Autodesk Inventor part; units mm, degrees
(part 2 of 2)
sketch "Boceto2" plane through (0, 0, 0) normal (0, 0, 1) x (1, 0, 0)
  spline S0 degree 3 poles (7.9309, 35.7631) (6.9516, 35.763) (3.1923, 28.7681) (4.1998, 28.3225) (4.6339, 28.1306) (10.2939, 27.728) (11.664, 28.3225) (12.6319, 28.7425) (8.957, 35.7632) (7.9309, 35.7631) knots 0 0 0 0 1 1 1 2 2 2 3 3 3 3 projected
  line L0 (7.3637, 34.0871) -> (8.4981, 34.0871) projected
  line L1 (7.4884, 30.4763) -> (7.3637, 34.0871) projected
  line L2 (8.4981, 34.0871) -> (8.3734, 30.4763) projected
  line L3 (8.3734, 30.4763) -> (7.4884, 30.4763) projected
  circle A0 centre (7.9309, 29.3763) radius 0.65 projected
  line L4 (32.3701, 25.3428) -> (32.3701, 0.7726)
  line L5 (32.3701, 7.2118) -> (27.7914, 7.2118)
  line L6 (27.7914, 7.2118) -> (27.7914, 6.0248)
  line L7 (26.7914, 5.0248) -> (26.4708, 5.0248)
  line L8 (25.4708, 6.0248) -> (25.4708, 7.2118)
  line L9 (25.4708, 7.2118) -> (24.0793, 7.2118)
  line L10 (24.0793, 7.2118) -> (24.0793, 14.3592)
  line L11 (24.0793, 14.3592) -> (24.8752, 19.7039)
  line L12 (26.1237, 21.2714) -> (26.3897, 21.3756)
  line L13 (31.8621, 22.4095) -> (32.3701, 22.4095)
  arc A1 (31.8621, 22.4095) -> (26.3897, 21.3756) centre (31.8621, 7.4095) ccw
  arc A2 (26.1237, 21.2714) -> (24.8752, 19.7039) centre (26.8534, 19.4093) ccw
  arc A3 (25.4708, 6.0248) -> (26.4708, 5.0248) centre (26.4708, 6.0248) ccw
  arc A4 (26.7914, 5.0248) -> (27.7914, 6.0248) centre (26.7914, 6.0248) ccw
  line L14 (32.3701, 21.0432) -> (28.8161, 21.0432)
  line L15 (28.4161, 20.6432) -> (28.4161, 20.6432)
  line L16 (28.8161, 20.2432) -> (32.3701, 20.2432)
  arc A5 (28.8161, 21.0432) -> (28.4161, 20.6432) centre (28.8161, 20.6432) ccw
  arc A6 (28.4161, 20.6432) -> (28.8161, 20.2432) centre (28.8161, 20.6432) ccw
  line L17 (32.3701, 19.3042) -> (26.6019, 19.3042)
  line L18 (26.2062, 18.9626) -> (25.5385, 14.4443)
  line L19 (25.9342, 13.9858) -> (32.3701, 13.9858)
  arc A7 (25.5385, 14.4443) -> (25.9342, 13.9858) centre (25.9342, 14.3858) ccw
  arc A8 (26.6019, 19.3042) -> (26.2062, 18.9626) centre (26.6019, 18.9042) ccw
  ellipse E0 centre (26.6311, 10.5064) end of major axis (25.5385, 10.5064) minor radius 0.9943
  line L20 (32.3701, 7.2118) -> (36.9488, 7.2118)
  line L21 (36.9488, 7.2118) -> (36.9488, 6.0248)
  line L22 (37.9488, 5.0248) -> (38.2694, 5.0248)
  line L23 (39.2694, 6.0248) -> (39.2694, 7.2118)
  line L24 (39.2694, 7.2118) -> (40.6609, 7.2118)
  line L25 (40.6609, 7.2118) -> (40.6609, 14.3592)
  line L26 (40.6609, 14.3592) -> (39.8649, 19.7039)
  line L27 (38.6164, 21.2714) -> (38.3505, 21.3756)
  line L28 (32.878, 22.4095) -> (32.3701, 22.4095)
  arc A9 (38.3505, 21.3756) -> (32.878, 22.4095) centre (32.878, 7.4095) ccw
  arc A10 (39.8649, 19.7039) -> (38.6164, 21.2714) centre (37.8867, 19.4093) ccw
  arc A11 (38.2694, 5.0248) -> (39.2694, 6.0248) centre (38.2694, 6.0248) ccw
  arc A12 (36.9488, 6.0248) -> (37.9488, 5.0248) centre (37.9488, 6.0248) ccw
  line L29 (32.3701, 21.0432) -> (35.9241, 21.0432)
  line L30 (36.3241, 20.6432) -> (36.3241, 20.6432)
  line L31 (35.9241, 20.2432) -> (32.3701, 20.2432)
  arc A13 (36.3241, 20.6432) -> (35.9241, 21.0432) centre (35.9241, 20.6432) ccw
  arc A14 (35.9241, 20.2432) -> (36.3241, 20.6432) centre (35.9241, 20.6432) ccw
  line L32 (32.3701, 19.3042) -> (38.1382, 19.3042)
  line L33 (38.5339, 18.9626) -> (39.2016, 14.4443)
  line L34 (38.8059, 13.9858) -> (32.3701, 13.9858)
  arc A15 (38.8059, 13.9858) -> (39.2016, 14.4443) centre (38.8059, 14.3858) ccw
  arc A16 (38.5339, 18.9626) -> (38.1382, 19.3042) centre (38.1382, 18.9042) ccw
  ellipse E1 centre (38.1091, 10.5064) end of major axis (39.2016, 10.5064) minor radius 0.9943
  line L35 (7.9309, 33.6763) -> (7.9309, 9.1164)
  line L36 (7.9309, 29.1763) -> (4.7309, 29.1763)
  line L37 (4.7309, 28.5763) -> (7.9309, 28.5763)
  arc A17 (4.7309, 29.1763) -> (4.4309, 28.8763) centre (4.7309, 28.8763) ccw
  arc A18 (4.4309, 28.8763) -> (4.7309, 28.5763) centre (4.7309, 28.8763) ccw
  arc A19 (11.1309, 28.5763) -> (11.4309, 28.8763) centre (11.1309, 28.8763) ccw
  arc A20 (11.4309, 28.8763) -> (11.1309, 29.1763) centre (11.1309, 28.8763) ccw
  line L38 (11.1309, 28.5763) -> (7.9309, 28.5763)
  line L39 (7.9309, 29.1763) -> (11.1309, 29.1763)
  line L40 (24.7872, 19.1125) -> (25.3084, 22.6124)
  line L41 (32.3947, 25.3417) -> (32.3701, 25.3428)
  arc A21 (32.3947, 25.3417) -> (26.8076, 24.5197) centre (31.7456, 10.3558) ccw
  line L42 (25.7305, 23.6251) -> (25.551, 23.3118)
  arc A22 (26.8076, 24.5197) -> (25.7305, 23.6251) centre (27.466, 22.6312) ccw
  arc A23 (25.551, 23.3118) -> (25.3084, 22.6124) centre (27.2865, 22.3178) ccw
  line L43 (39.953, 19.1125) -> (39.4318, 22.6124)
  arc A24 (37.9325, 24.5197) -> (32.3454, 25.3417) centre (32.9946, 10.3558) ccw
  line L44 (39.0097, 23.6251) -> (39.1891, 23.3118)
  arc A25 (39.0097, 23.6251) -> (37.9325, 24.5197) centre (37.2741, 22.6312) ccw
  arc A26 (39.4318, 22.6124) -> (39.1891, 23.3118) centre (37.4536, 22.3178) ccw
  line L45 (24.0793, 8.0227) -> (-63.9207, 8.0227)
  line L46 (24.0793, 11.5227) -> (-63.9207, 11.5227)
  line L47 (-65.9207, 13.5227) -> (-65.9207, 21.5227)
  line L48 (-65.9207, 6.0227) -> (-65.9207, -1.9773)
  line L49 (-69.9207, -1.9773) -> (-69.9207, 21.5227)
  arc A27 (-67.9207, 23.5227) -> (-69.9207, 21.5227) centre (-67.9207, 21.5227) ccw
  arc A28 (-65.9207, 21.5227) -> (-67.9207, 23.5227) centre (-67.9207, 21.5227) ccw
  arc A29 (-67.9207, -3.9773) -> (-65.9207, -1.9773) centre (-67.9207, -1.9773) ccw
  arc A30 (-69.9207, -1.9773) -> (-67.9207, -3.9773) centre (-67.9207, -1.9773) ccw
  arc A31 (-63.9207, 8.0227) -> (-65.9207, 6.0227) centre (-63.9207, 6.0227) ccw
  arc A32 (-65.9207, 13.5227) -> (-63.9207, 11.5227) centre (-63.9207, 13.5227) ccw
  line L50 (40.6609, 8.0227) -> (74.1609, 8.0227)
  line L51 (75.6609, 9.5227) -> (75.6609, 10.0227)
  line L52 (74.1609, 11.5227) -> (40.6609, 11.5227)
  line L53 (-16.0296, 22.7659) -> (-11.0296, 22.7659)
  line L54 (-11.0296, 22.7659) -> (-11.0296, 16.7659)
  line L55 (-11.0296, 16.7659) -> (-16.0296, 16.7659)
  line L56 (-11.0296, 19.7659) -> (-19.4903, 19.7659)
  line L57 (-16.0296, 22.7659) -> (-16.0296, 21.6659)
  line L58 (-16.0296, 21.6659) -> (-14.4296, 21.6659)
  line L59 (-14.4296, 21.6659) -> (-14.4296, 17.8659)
  line L60 (-14.4296, 17.8659) -> (-16.0296, 17.8659)
  line L61 (-16.0296, 17.8659) -> (-16.0296, 16.7659)
  arc A33 (75.6609, 10.0227) -> (74.1609, 11.5227) centre (74.1609, 10.0227) ccw
  arc A34 (74.1609, 8.0227) -> (75.6609, 9.5227) centre (74.1609, 9.5227) ccw
  point P0 (0, 0)
  point P1 (7.9309, 35.7631)
  point P2 (28.4161, 21.0432)
  point P3 (28.4161, 20.2432)
  point P4 (36.3241, 21.0432)
  point P5 (36.3241, 20.2432)
  point P6 (25.5317, 24.1125)
  point P7 (26.0869, 24.2475)
  point P8 (26.0869, 24.2475)
  point P9 (-65.9207, 8.0227)
  point P10 (-65.9207, 11.5227)
  point P11 (-65.9207, 23.5227)
  point P12 (-69.9207, 23.5227)
  point P13 (-65.9207, -3.9773)
  point P14 (-69.9207, -3.9773)
  point P15 (-67.9207, 23.5227)
  point P16 (-67.9207, -3.9773)
  point P17 (32.3703, 25.3428)
  point P18 (75.6609, 8.0227)
  point P19 (75.6609, 11.5227)
  point P20 (7.3124, 29.1763)
  point P21 (8.5494, 29.1763)
  dimension "d5" = 15
  dimension "d6" = 2
  dimension "d7" = 1
  dimension "d8" = 0.8
  dimension "d9" = 0.4
  dimension "d10" = 0.4
  dimension "d11" = 0.3
  dimension "d12" = 0.6
  dimension "d13" = 7
  dimension "d14" = 81.53
  dimension "d15" = 16.5816
  dimension "d16" = 14.9897
  dimension "d17" = 5
  dimension "d18" = 15
  dimension "d20" = 2
  dimension "d21" = 90
  dimension "d22" = 90
  dimension "d23" = 3.5
  dimension "d24" = 12
  dimension "d25" = 4
  dimension "d26" = 12
  dimension "d27" = 4
  dimension "d28" = 2
  dimension "d41" = 35
  dimension "d42" = 5
  dimension "d43" = 6
  dimension "d44" = 3.8
  dimension "d47" = 1.5
  dimension "d48" = 1.6
  constraints: 116 end point, 67 point on circle, 46 symmetric about line, 40 point on line, 35 centre point, 35 tangent, 18 horizontal, 13 vertical, 11 equal radius, 3 collinear, 1 midpoint, 33 other
  measures "d5" radius of A1
  measures "d6" radius of A2
  measures "d7" radius of A3
  measures "d8" distance of point (28.416, 21.043) point (28.416, 20.243)
  measures "d9" radius of A5
  measures "d10" radius of A7
  measures "d11" radius of A17
  measures "d12" distance between parallel lines of L37 L36
  measures "d13" distance of A17.end A20.start
  measures "d14" angle of L19 L11
  measures "d15" distance of L26.start L10.end
  measures "d16" distance of L26.end L11.end
  measures "d17" vertical distance of L40.start point (25.532, 24.113)
  measures "d18" radius of A21
  measures "d20" radius of A22
  measures "d21" distance of L45.start point (-65.921, 8.023)
  measures "d22" distance of L46.start point (-65.921, 11.523)
  measures "d23" distance between parallel lines of L45 L46
  measures "d24" distance of point (-65.921, 11.523) point (-65.921, 23.523)
  measures "d25" distance of point (-65.921, 23.523) point (-69.921, 23.523)
  measures "d26" distance of point (-65.921, 8.023) point (-65.921, -3.977)
  measures "d27" distance of point (-65.921, -3.977) point (-69.921, -3.977)
  measures "d28" radius of A27
  measures "d41" distance of point (75.661, 11.523) L52.end
  measures "d42" distance of L53.start L53.end
  measures "d43" distance of L53.end L54.end
  measures "d44" distance of L58.end L59.end
  measures "d47" radius of A33
  measures "d48" distance between parallel lines of L59 L57
extrude "Extrusión1" add sketch "Boceto2" along normal blind 2.5 contours L28 A9 L27 A10 L26 L25 L24 L23 A11 L22 A12 L21 L20 L4 L34 A15 L33 A16 L32 L31 A14 A13 L29 | L4 L14 A5 A6 L16 L17 A8 L18 A7 L19 L5 L6 A4 L7 A3 L8 L9 L10 L11 A2 L12 A1 L13
extrude "Extrusión2" add sketch "Boceto2" along normal blind 1.5 contours L32 A16 L33 A15 L34 L4 | L4 L19 A7 L18 A8 L17 | E0 | E1
extrude "Extrusión3" add sketch "Boceto2" along normal blind 1 contours L29 A13 A14 L31 L4 | L4 L16 A6 A5 L14
extrude "Extrusión4" add sketch "Boceto2" along normal blind 1.2 contours L10 L45 A31 L48 A29 A30 L49 A27 A28 L47 A32 L46 | L52 A33 L51 A34 L50 L25
extrude "Extrusión6" add sketch "Boceto2" along normal blind 3.5 contours L53 L54 L56 L59 L58 L57 | L54 L55 L61 L60 L59 L56
extrude "Extrusion7" add sketch "Boceto2" along normal blind 2 contours S0 | L39 A20 A19 L38 L35 A0 | A0 L35 L37 A18 A17 L36
extrude "Extrusion8" add sketch "Boceto2" along normal blind 1 contours L0 L2 L3 L1 | A0 L39 L35 | L35 L36 A0 | A0 L35 L39 | L36 L35 A0
extrude "Extrusion9" add sketch "Boceto2" against normal blind 1 contours L39 A20 A19 L38 L35 A0 | A0 L35 L37 A18 A17 L36
